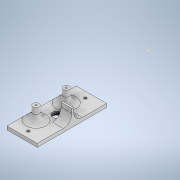
# Autodesk Inventor part: Part45asta e
Saved by Autodesk Inventor 2022.6 (Build 266554000, 554)
## iProperties
Created: 2026-10-28
Part Number: Part45asta e
Material: Generic
Document SubType Name: Modeling
Designer: Dragos Macovei
Density: 1 g/cm^3
Appearance: Default
Author: Dragos Macovei
Autodesk Inventor part; units mm, degrees
ref_plane "YZ Plane" through (0, 0, 0) normal (1, 0, 0) x (0, 1, 0)
ref_plane "XZ Plane" through (0, 0, 0) normal (0, 1, 0) x (-1, 0, 0)
ref_plane "XY Plane" through (0, 0, 0) normal (0, 0, 1) x (1, 0, 0)
sketch "Sketch1" plane through (0, 0, 0) normal (0, 1, 0) x (-1, 0, 0)
  circle A0 centre (-10.9929, 149.7887) radius 1.6
  circle A1 centre (-10.9929, 83.7887) radius 1.6
  line L0 (6.5071, 156.7887) -> (-28.4929, 156.7887)
  line L1 (-28.4929, 156.7887) -> (-28.4929, 76.7887)
  line L2 (-28.4929, 76.7887) -> (6.5071, 76.7887)
  line L3 (6.5071, 76.7887) -> (6.5071, 156.7887)
  point P0 (0, 0)
  point P1 (-10.9929, 156.7887)
  dimension "d0" = 66
  dimension "d1" = 17.5
  dimension "d2" = 35
  dimension "d3" = 17.5
  dimension "d4" = 3.2
  dimension "d5" = 3.2
  dimension "d6" = 80
  dimension "d7" = 7
  constraints: 8 end point, 2 centre point, 2 parallel, 1 horizontal, 1 midpoint, 1 perpendicular
  measures "d0" distance of A1.centre A0.centre
  measures "d1" distance from line of L3 A0.centre
  measures "d2" distance of L0.start L0.end
  measures "d3" distance from line of L3 A1.centre
  measures "d4" diameter of A0
  measures "d5" diameter of A1
  measures "d6" distance of L2.end L0.start
  measures "d7" distance of point (-10.993, 156.789) A0.centre
extrude "Extrusion1" add sketch "Sketch1" along normal blind 4
sketch "Sketch2" plane through (0, 4, 0) normal (0, 1, 0) x (1, 0, 0)
  line L0 (28.4929, -156.7887) -> (28.4929, -76.7887) projected
  line L1 (28.4929, -76.7887) -> (-6.5071, -76.7887) projected
  line L2 (-6.5071, -76.7887) -> (-6.5071, -156.7887) projected
  line L3 (-6.5071, -156.7887) -> (28.4929, -156.7887) projected
  circle A0 centre (10.9929, -149.7887) radius 1.6 projected
  circle A1 centre (10.9929, -83.7887) radius 1.6 projected
  circle A2 centre (4.4929, -134.2887) radius 1.15
  circle A3 centre (4.4929, -99.2887) radius 1.15
  line L4 (-6.5071, -76.7887) -> (-6.5071, -156.7887) projected
  line L5 (28.4929, -156.7887) -> (28.4929, -76.7887) projected
  line L6 (-6.5071, -116.7887) -> (28.4929, -116.7887)
  circle A4 centre (4.4929, -99.2887) radius 3.5
  circle A5 centre (10.9929, -149.7887) radius 1.6 projected
  line L7 (10.9929, -149.7887) -> (10.9929, -83.7887)
  circle A6 centre (4.4929, -134.2887) radius 3.5
  point P0 (0, 0)
  dimension "d10" = 35
  dimension "d11" = 17.5
  dimension "d13" = 7
  dimension "d14" = 2.3
  dimension "d15" = 2.3
  dimension "d28" = 6.5
  dimension "d29" = 6.5
  dimension "d30" = 7
  constraints: 4 centre point, 4 end point, 2 coincident, 2 midpoint, 1 perpendicular, 1 vertical
  measures "d10" distance of A2.centre A3.centre
  measures "d11" distance from line of L6 A2.centre
  measures "d13" diameter of A4
  measures "d14" diameter of A2
  measures "d15" diameter of A3
  measures "d28" distance from line of L7 A3.centre
  measures "d29" distance from line of L7 A2.centre
  measures "d30" diameter of A6
extrude "Extrusion2" add sketch "Sketch2" along normal blind 15 contours A4 | A6
fillet "Fillet1" radius 8 2 edges at (0.9929, 4, 99.2887) (0.9929, 4, 134.2887)
sketch "Sketch3" plane through (0, 4, 0) normal (0, 1, 0) x (1, 0, 0)
  line L0 (28.4929, -156.7887) -> (28.4929, -76.7887) projected
  line L1 (28.4929, -76.7887) -> (-6.5071, -76.7887) projected
  line L2 (-6.5071, -76.7887) -> (-6.5071, -95.9346) projected
  line L3 (-6.5071, -156.7887) -> (28.4929, -156.7887) projected
  circle A0 centre (10.9929, -149.7887) radius 1.6 projected
  circle A1 centre (10.9929, -83.7887) radius 1.6 projected
  arc A2 (-6.5071, -102.6428) -> (-6.5071, -95.9346) centre (4.4929, -99.2887) ccw projected
  circle A3 centre (10.9929, -116.7887) radius 5
  circle A4 centre (10.9929, -149.7887) radius 1.6 projected
  line L4 (10.9929, -149.7887) -> (10.9929, -83.7887)
  line L5 (-6.5071, -102.6428) -> (-6.5071, -130.9346) projected
  arc A5 (-6.5071, -137.6428) -> (-6.5071, -130.9346) centre (4.4929, -134.2887) ccw projected
  line L6 (-6.5071, -137.6428) -> (-6.5071, -156.7887) projected
  point P0 (0, 0)
  dimension "d19" = 10
  dimension "d20" = 33
  constraints: 2 end point, 1 centre point, 1 vertical
  measures "d19" diameter of A3
  measures "d20" distance of L4.end A3.centre
extrude "Extrusion3" cut sketch "Sketch3" against normal blind 15 contours L4 A3 | A3 L4
sketch "Sketch4" plane through (0, 4, 0) normal (0, 1, 0) x (1, 0, 0)
  circle A0 centre (10.9929, -116.7887) radius 5 projected
  line L0 (28.4929, -156.7887) -> (28.4929, -76.7887) projected
  line L1 (28.4929, -76.7887) -> (-6.5071, -76.7887) projected
  line L2 (-6.5071, -76.7887) -> (-6.5071, -95.9346) projected
  line L3 (-6.5071, -156.7887) -> (28.4929, -156.7887) projected
  circle A1 centre (10.9929, -149.7887) radius 1.6 projected
  circle A2 centre (10.9929, -83.7887) radius 1.6 projected
  arc A3 (-6.5071, -102.6428) -> (-6.5071, -95.9346) centre (4.4929, -99.2887) ccw projected
  circle A4 centre (10.9929, -116.7887) radius 5 projected
  line L4 (28.4929, -156.7887) -> (28.4929, -76.7887) projected
  line L5 (15.9929, -116.7887) -> (28.4929, -116.7887)
  line L6 (28.4929, -116.7887) -> (28.4929, -114.7887)
  line L7 (28.4929, -114.7887) -> (15.9929, -114.7887)
  line L8 (15.9929, -114.7887) -> (15.9929, -116.7887)
  line L9 (-6.5071, -102.6428) -> (-6.5071, -130.9346) projected
  arc A5 (-6.5071, -137.6428) -> (-6.5071, -130.9346) centre (4.4929, -134.2887) ccw projected
  line L10 (-6.5071, -137.6428) -> (-6.5071, -156.7887) projected
  point P0 (0, 0)
  dimension "d23" = 2
  constraints: 8 end point, 2 parallel, 1 horizontal, 1 horizontal alignment, 1 perpendicular, 1 point on line, 1 other
  measures "d23" distance of L6.end L5.end
extrude "Extrusion4" add sketch "Sketch4" along normal blind 15 contours L8 L7 L0 L5
fillet "Fillet2" radius 10 2 edges at (22.2429, 4, 116.7887) (22.2429, 4, 114.7887)
sketch "Sketch5" plane through (0, 4, 0) normal (0, 1, 0) x (1, 0, 0)
  point P0 (0, 0)
equation "\"d3\" = d1"
equation "\"d5\" = d4"
equation "\"d29\" = d28"
body "Solid1"
